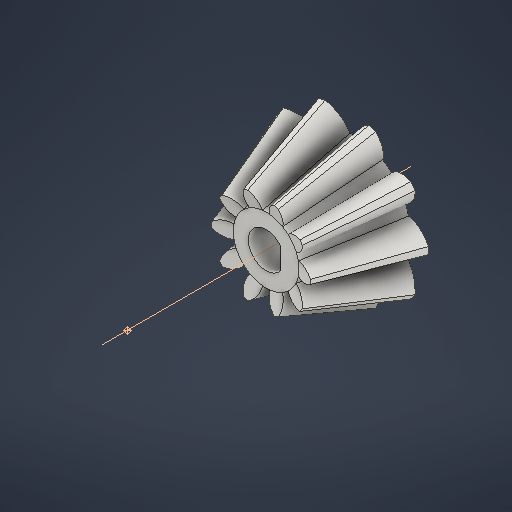
# Autodesk Inventor part: Przekładnia stożkowa2
Saved by Autodesk Inventor 2026.1 (Build 301233020, 233B)
## iProperties
Created: 2026-01-08
Part Number: Przekładnia stożkowa2
Material: Steel, Mild
Document SubType Name: Modeling
Designer: Nitro
Categories: <?xml version="1.0" encoding="UTF-16"?> <MemberInstance><Categories><FamilyTemplate><FamilyTemplateParameter ValueType="xs:double" Id="1" ObjectReferenceKey="da_z" ObjectType="kUserParameterObject"/><FamilyTemplateParameter ValueType="xs:double" Id="2" ObjectReferenceKey="da_b" ObjectType="kUserParameterObject"/><FamilyTemplateParameter ValueType="xs:double" Id="3" ObjectReferenceKey="da_beta" ObjectType="kUserParameterObject"/><FamilyTemplateParameter ValueType="xs:double" Id="4" ObjectReferenceKey="da_dae" ObjectType="kUserParameterObject"/><FamilyTemplateParameter ValueType="xs:double" Id="5" ObjectReferenceKey="da_ve" ObjectType="kUserParameterObject"/><FamilyTemplateParameter ValueType="xs:double" Id="6" ObjectReferenceKey="da_omega" ObjectType="kUserParameterObject"/><FamilyTemplateParameter ValueType="xs:string" Id="7" ObjectReferenceKey="EAIAABAAAAAAHwAAAAAAAIAAAAAAAAAA" ObjectType="83914240" SubObjectId="SurfaceGeometry"/></FamilyTemplate><ParamToTemplateMap><ParamToTemplate CategoryParameter="//CategoryParameter[@InternalName='046C89C9-8512-4d59-83FE-43B91F4F132A']" TemplateParameter="1"/><ParamToTemplate CategoryParameter="//CategoryParameter[@InternalName='2552DF32-E462-4b46-AEBF-C6C7768E72AC']" TemplateParameter="2"/><ParamToTemplate CategoryParameter="//CategoryParameter[@InternalName='C9EE641D-15FC-4fae-A226-E94C4372FDD7']" TemplateParameter="3"/><ParamToTemplate><ParamToTemplate CategoryParameter="//CategoryParameter[@InternalName='00B6519A-459B-49c7-AD84-2E56D39A5744']" ConstantValue="-0.000000"/></ParamToTemplate><ParamToTemplate><ParamToTemplate CategoryParameter="//CategoryParameter[@InternalName='04B31F0E-C7A6-4894-AA32-9629BEFACF47']" ConstantValue="1.000000"/></ParamToTemplate><ParamToTemplate><ParamToTemplate CategoryParameter="//CategoryParameter[@InternalName='43CBEC2E-7847-49e7-A936-2F7889FCB2D9']" ConstantValue="0.200000"/></ParamToTemplate><ParamToTemplate><ParamToTemplate CategoryParameter="//CategoryParameter[@InternalName='B1EFC894-105D-4ebd-86BF-FA20ED196853']" ConstantValue="0.300000"/></ParamToTemplate><ParamToTemplate><ParamToTemplate CategoryParameter="//CategoryParameter[@InternalName='51175063-3D10-4879-93E8-6246FE8B403D']" ConstantValue="2060000000.000000"/></ParamToTemplate><ParamToTemplate><ParamToTemplate CategoryParameter="//CategoryParameter[@InternalName='A3A52E27-4454-46a9-B0BD-C932399B70AF']" ConstantValue="0.300000"/></ParamToTemplate><ParamToTemplate CategoryParameter="//CategoryParameter[@InternalName='2A200944-5A8C-41ca-B96E-8520D2E510F1']" TemplateParameter="4"/><ParamToTemplate><ParamToTemplate CategoryParameter="//CategoryParameter[@InternalName='1A637F62-92C8-44bc-B81F-10802510B579']" ConstantValue="1.420783"/></ParamToTemplate><ParamToTemplate CategoryParameter="//CategoryParameter[@InternalName='B52DD4BE-6863-48fb-BF58-89EF6F9EC65C']" TemplateParameter="5"/><ParamToTemplate><ParamToTemplate CategoryParameter="//CategoryParameter[@InternalName='3956BFF2-84D2-457d-93C2-9B0613DEBA67']" ConstantValue="1.918028"/></ParamToTemplate><ParamToTemplate CategoryParameter="//CategoryParameter[@InternalName='739CFA02-461B-4bf8-8049-181FCAD8B28F']" TemplateParameter="6"/><ParamToTemplate><ParamToTemplate CategoryParameter="//CategoryParameter[@InternalName='A27E999F-E2CE-4481-8A2A-EBF499C4C3C5']" ConstantValue="-0.000000"/></ParamToTemplate><ParamToTemplate><ParamToTemplate CategoryParameter="//CategoryParameter[@InternalName='9E1B4470-B2D3-4ff1-B813-535BB4CDF51A']" ConstantValue="3520000.000000"/></ParamToTemplate><ParamToTemplate><ParamToTemplate CategoryParameter="//CategoryParameter[@InternalName='F8452263-BFF6-458c-9FB1-07C4B99E95CD']" ConstantValue="11400000.000000"/></ParamToTemplate><ParamToTemplate><ParamToTemplate CategoryParameter="//CategoryParameter[@InternalName='3E3BB259-FD49-497f-8171-6EBC954A3479']" ConstantValue="2.000000"/></ParamToTemplate><ParamToTemplate CategoryParameter="//CategoryParameter[@InternalName='27C3BAF2-7550-4e4b-AE2C-0DB134B7D9B7']" TemplateParameter="7"/></ParamToTemplateMap><Category DisplayName="Gear" InternalName="DC85795E-93AB-48d5-8EEE-5A27447B64BD" Mnemonic="Gear"><CategoryParameter DisplayName="z" InternalName="046C89C9-8512-4d59-83FE-43B91F4F132A" Mnemonic="z"/><CategoryParameter DisplayName="b" InternalName="2552DF32-E462-4b46-AEBF-C6C7768E72AC" Mnemonic="b"/><CategoryParameter DisplayName="||b|" InternalName="C9EE641D-15FC-4fae-A226-E94C4372FDD7" Mnemonic="beta"/><CategoryParameter DisplayName="x" InternalName="00B6519A-459B-49c7-AD84-2E56D39A5744" Mnemonic="x"/><CategoryParameter DisplayName="a*" InternalName="04B31F0E-C7A6-4894-AA32-9629BEFACF47" Mnemonic="a"/><CategoryParameter DisplayName="c*" InternalName="43CBEC2E-7847-49e7-A936-2F7889FCB2D9" Mnemonic="c"/><CategoryParameter DisplayName="r|.f|*" InternalName="B1EFC894-105D-4ebd-86BF-FA20ED196853" Mnemonic="rf"/><CategoryParameter DisplayName="E" InternalName="51175063-3D10-4879-93E8-6246FE8B403D" Mnemonic="E"/><CategoryParameter DisplayName="||m|" InternalName="A3A52E27-4454-46a9-B0BD-C932399B70AF" Mnemonic="mi"/><Category DisplayName="BevelGear" InternalName="0C98F69A-0C2B-4791-B2FE-7691BB227E77" Mnemonic="BevelGear"><CategoryParameter DisplayName="d|.ae|" InternalName="2A200944-5A8C-41ca-B96E-8520D2E510F1" Mnemonic="dae"/><CategoryParameter DisplayName="d|.ai|" InternalName="1A637F62-92C8-44bc-B81F-10802510B579" Mnemonic="dai"/><CategoryParameter DisplayName="A|.e|" InternalName="B52DD4BE-6863-48fb-BF58-89EF6F9EC65C" Mnemonic="ve"/><CategoryParameter DisplayName="A|.i|" InternalName="3956BFF2-84D2-457d-93C2-9B0613DEBA67" Mnemonic="vi"/><CategoryParameter DisplayName="||S|" InternalName="739CFA02-461B-4bf8-8049-181FCAD8B28F" Mnemonic="omega"/><CategoryParameter DisplayName="x|.t|" InternalName="A27E999F-E2CE-4481-8A2A-EBF499C4C3C5" Mnemonic="xt"/><CategoryParameter DisplayName="||s||.Flim|" InternalName="9E1B4470-B2D3-4ff1-B813-535BB4CDF51A" Mnemonic="sFlim"/><CategoryParameter DisplayName="||s||.Hlim|" InternalName="F8452263-BFF6-458c-9FB1-07C4B99E95CD" Mnemonic="sHlim"/><CategoryParameter DisplayName="typ" InternalName="3E3BB259-FD49-497f-8171-6EBC954A3479" Mnemonic="type"/><CategoryParameter DisplayName="PitchDiameter" InternalName="27C3BAF2-7550-4e4b-AE2C-0DB134B7D9B7" Mnemonic="IDS_PITCHDIAM"/></Category></Category></Categories></MemberInstance>
Mass: 60.9118 g
Surface Area: 34.3074 cm^2
Volume: 7.7496 cm^3
Density: 7.86 g/cm^3
Appearance: Steel
CustomPartVersion: 1
Author: Nitro
Autodesk Inventor part; units mm, degrees
ref_plane "Płaszczyzna zazębienia2" through (0, 0, 0) normal (0.9510565, 0.309017, 0) x (0, 0, 1)
sketch "Szkic bryły z zębami" plane through (0, 0, 0) normal (1, 0, 0) x (0, 1, 0)
  line L0 (0, 0) -> (7.7092, -32.7159) construction
  line L1 (7.7092, -32.7159) -> (11.6599, -31.4813)
  line L2 (11.6599, -31.4813) -> (0, 0) construction
  line L3 (10, -32) -> (0, 0) construction
  line L4 (4.6969, -19.9325) -> (7.1039, -19.1803)
  line L5 (7.7092, -32.7159) -> (4.6969, -19.9325)
  line L6 (11.6599, -31.4813) -> (7.1039, -19.1803)
  line L7 (0, -39.3868) -> (0, 6.5645) projected
  line L8 (0, -32) -> (11.6599, -32) construction
  dimension "d0" = 20
  dimension "d1" = 15.4185
  dimension "d2" = 23.3198
  dimension "d3" = 13.1
  dimension "d4" = 31.4813
  constraints: 16 end point, 4 point on line, 3 perpendicular, 2 collinear, 1 horizontal alignment, 1 vertical alignment
  measures "d0" diameter of L3.start L7
  measures "d1" diameter of L0.end L7
  measures "d2" diameter of L1.end L7
  measures "d3" distance between parallel lines of L1 L4
  measures "d4" vertical distance of L1.end L0.start
revolve "Bryła z zębami" add sketch "Szkic bryły z zębami" angle 360 about axis through (0, 0, 0) along (0, 0, 1)
ref_plane "Płaszczyzna zęba" through (0, 10, -32) normal (0, -0.298275, 0.95448) x (1, 0, 0)
sketch "Początek szkicu" plane through (0, 10, -32) normal (0, -0.298275, 0.95448) x (1, 0, 0)
  line L0 (0, -23.5051) -> (0, 10.6448) projected
  arc A0 (-0.8252, -2.8967) -> (-5.1657, 1.9499) centre (-5.4411, -2.6636) ccw
  arc A1 (5.1657, 1.9499) -> (0.8252, -2.8967) centre (5.4411, -2.6636) ccw
  line L1 (-0.8252, -2.8967) -> (0.8252, -2.8967)
  arc A2 (5.1657, 1.9499) -> (-5.1657, 1.9499) centre (0, -10.4769) ccw
  dimension "d7" = 4.6217
  dimension "d8" = 5.4411
  dimension "d9" = 7.8133
  dimension "d57" = 13.4577
  dimension "d58" = 7.5802
  constraints: 6 point on circle, 3 centre point, 3 symmetric about line, 2 end point, 1 coincident, 1 perpendicular, 1 other
  measures "d7" radius of A0
  measures "d8" horizontal distance of point (0, -10.477) A0.centre
  measures "d9" vertical distance of point (0, -10.477) A0.centre
  measures "d57" radius of A2
  measures "d58" distance from line of A2.centre L1
ref_plane "Płaszczyzna końcowa" through (0, 6.0309, -19.2988) normal (0, -0.298275, 0.95448) x (1, 0, 0)
sketch "Zakończenie szkicu" plane through (0, 6.0309, -19.2988) normal (0, -0.298275, 0.95448) x (1, 0, 0)
  line L0 (0, -15.354) -> (0, 6.9534) projected
  arc A0 (-0.4977, -1.747) -> (-3.1154, 1.1759) centre (-3.2814, -1.6064) ccw
  arc A1 (3.1154, 1.1759) -> (0.4977, -1.747) centre (3.2814, -1.6064) ccw
  line L1 (-0.4977, -1.747) -> (0.4977, -1.747)
  arc A2 (3.1154, 1.1759) -> (-3.1154, 1.1759) centre (0, -6.3185) ccw
  dimension "d12" = 2.7873
  dimension "d15" = 3.2814
  dimension "d16" = 4.7121
  dimension "d59" = 8.1162
  dimension "d60" = 4.5715
  constraints: 6 point on circle, 3 centre point, 3 symmetric about line, 2 end point, 1 coincident, 1 other
  measures "d12" radius of A0
  measures "d15" horizontal distance of A0.centre point (0, -6.318)
  measures "d16" vertical distance of A0.centre point (0, -6.318)
  measures "d59" radius of A2
  measures "d60" distance from line of A2.centre L1
loft "Loft" cut profiles "Początek szkicu", "Zakończenie szkicu"
pattern_circular "Circular Pattern" count 10 over 360 about axis through (0, 0, 0) along (0, 0, 1) of "Loft"
sketch3d "Prawy szkic 3D"
ref_plane "Powierzchnia końcowa prawa" through (-3.4149, 4.9709, -19.2988) normal (0.1688943, -0.2458509, 0.95448) x (0.8242425, 0.566237, 0)
sketch "Koniec szkicu prawy" plane through (-3.4149, 4.9709, -19.2988) normal (0.1688943, -0.2458509, 0.95448) x (0.8242425, 0.566237, 0)
  arc A0 (-0.4977, -1.747) -> (-3.1154, 1.1759) centre (-3.2814, -1.6064) ccw
  line L0 (0, -23.572) -> (0, 15.1714) projected
  arc A1 (3.1154, 1.1759) -> (0.4977, -1.747) centre (3.2814, -1.6064) ccw
  line L1 (-0.4977, -1.747) -> (0.4977, -1.747)
  arc A2 (3.1154, 1.1759) -> (-3.1154, 1.1759) centre (0, -6.3185) ccw
  dimension "d70" = 3.2814
  dimension "d71" = 4.7121
  dimension "d72" = 2.7873
  dimension "d73" = 4.5715
  dimension "d74" = 8.1162
  constraints: 6 point on circle, 3 centre point, 3 symmetric about line, 2 end point, 1 coincident, 1 perpendicular, 1 other
  measures "d70" horizontal distance of A2.centre A0.centre
  measures "d71" vertical distance of point (0, -6.318) A0.centre
  measures "d72" radius of A0
  measures "d73" distance from line of point (0, -6.318) L1
  measures "d74" radius of A2
feature "Wyciągnięcie prawe" [suppressed]
pattern_circular "Szyk kołowy prawy" [suppressed]
sketch3d "Lewy szkic 3D"
ref_plane "Powierzchnia końcowa lewa" through (3.338, 4.9709, -19.2784) normal (-0.1653563, -0.2462449, 0.9549978) x (0.8301892, -0.5574817, 0)
sketch "Koniec szkicu lewy" plane through (3.338, 4.9709, -19.2784) normal (-0.1653563, -0.2462449, 0.9549978) x (0.8301892, -0.5574817, 0)
  line L0 (0, -41.9767) -> (0, 24.954) projected
  arc A0 (-0.4977, -1.7117) -> (-3.1154, 1.2112) centre (-3.2814, -1.5712) ccw
  arc A1 (3.1154, 1.2112) -> (0.4977, -1.7117) centre (3.2814, -1.5712) ccw
  line L1 (-0.4977, -1.7117) -> (0.4977, -1.7117)
  ellipse E0 centre (0, -5.6891) end of major axis (7.1039, -5.6891) minor radius 6.7842 projected
  arc A2 (3.1154, 1.2112) -> (-3.1154, 1.2112) centre (0, -6.2833) ccw
  dimension "d56" = 6.7842
  dimension "d30" = 2.7873
  dimension "d31" = 3.2814
  dimension "d32" = 4.7121
  dimension "d61" = 8.1162
  dimension "d62" = 4.5715
  constraints: 6 point on circle, 3 centre point, 3 symmetric about line, 2 end point, 1 coincident, 2 other
  measures "d30" radius of A0
  measures "d31" horizontal distance of point (0, -6.283) A0.centre
  measures "d32" vertical distance of A0.centre point (0, -6.283)
  measures "d61" radius of A2
  measures "d62" distance from line of point (0, -6.283) L1
feature "Wyciągnięcie lewe" [suppressed]
pattern_circular "Szyk kołowy lewy" [suppressed]
sketch "Szkic bryły" plane through (0, 0, 0) normal (1, 0, 0) x (0, 1, 0)
  line L0 (0, -35.0375) -> (0, -19.5308) projected
  line L1 (7.7092, -32.7159) -> (4.6969, -19.9325) projected
  line L2 (4.6969, -19.9325) -> (0, -19.9325)
  line L3 (7.7092, -32.7159) -> (0, -32.7159)
  constraints: 4 end point, 2 perpendicular, 2 point on line
revolve "Ustal bryłę" add sketch "Szkic bryły" angle 360 about axis through (0, 0, 0) along (0, 0, 1)
sketch "Sketch6" plane through (0, 0, 0) normal (1, 0, 0) x (0, 1, 0)
  line L0 (10, -32) -> (0, 0) projected
  line L1 (0, -37.7999) -> (0, 6.3) projected
surface revolve "Średnica podziałowa" sketch "Sketch6" angle 360 about axis through (0, 0, 0) along (0, 0, 1) shown no curves L0
sketch "Szkic8" plane through (0, 0, -19.9325) normal (0, 0, 1) x (1, 0, 0)
  circle A0 centre (0, 0) radius 2.55
  line L0 (0, 0) -> (2.05, 0)
  line L1 (2.05, 0) -> (2.05, 1.5166)
  line L2 (2.05, 0) -> (2.05, -1.5166)
  dimension "d94" = 5.1
  dimension "d95" = 2.05
  constraints: 6 end point, 2 point on circle, 1 centre point, 1 coincident, 1 horizontal, 1 perpendicular, 1 point on line
  measures "d94" diameter of A0
  measures "d95" distance of L0.start L0.end
extrude "Wyciągnięcie proste1" cut sketch "Szkic8" against normal blind 20 contours L1 L2 A0 picked at (-1.0046, 0)
equation "\"d0\" = da_de"
equation "\"d1\" = da_dfe"
equation "\"d2\" = da_dae"
equation "\"d3\" = da_b"
equation "\"d4\" = da_ve"
equation "\"d7\" = fd_rr"
equation "\"d8\" = fd_x"
equation "\"d9\" = fd_y"
equation "\"d57\" = 0.5 * fd_dva + 0.3 * da_he"
equation "\"d58\" = 0.5 * fd_dva - 1.12 * da_he"
equation "\"da_teethtype\" = 0"
equation "\"da_b\" = 13.1"
equation "\"da_de\" = 20"
equation "\"da_dae\" = 23.31983"
equation "\"da_dfe\" = 15.4185"
equation "\"da_le\" = 33.52611"
equation "\"da_omega\" = 90deg"
equation "\"da_beta\" = 0"
equation "\"da_delta\" = 17.354025deg"
equation "\"da_alpha\" = 25deg"
equation "\"da_he\" = 4.13908"
equation "\"da_ve\" = 31.48128"
equation "\"da_zv\" = 10.476909"
equation "\"fd_loft\" = da_b + 0.05 * da_he"
equation "\"fd_x\" = fd_x1 + fd_x2"
equation "\"fd_y\" = fd_y1 - fd_y2"
equation "\"fd_dd\" = fd_dva - 0.8 * da_he"
equation "\"da_dvw\" = 20.95382"
equation "\"d11\" = fd_loft"
equation "\"da_dm\" = 16.0926"
equation "\"da_x\" = 0"
equation "\"da_m\" = 2"
equation "\"d50\" = da_omega"
equation "\"fd_rr\" = 4.62172"
equation "\"fd_dva\" = 24.431971"
equation "\"fd_x1\" = 1.582173"
equation "\"fd_x2\" = 3.858891"
equation "\"fd_y1\" = 10.356754"
equation "\"fd_y2\" = 2.543473"
body "Solid1"
body "Srf1"
